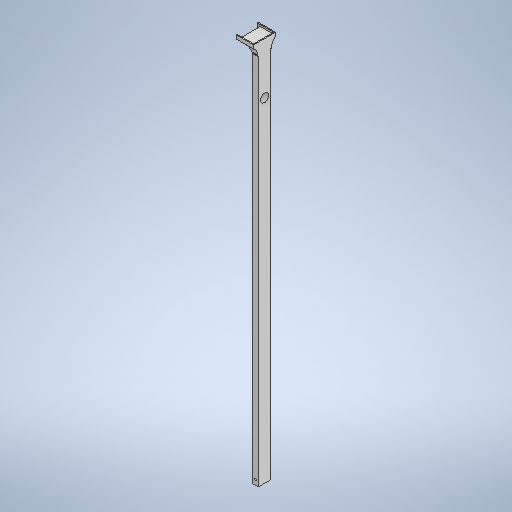
# Autodesk Inventor part: iterasi3-cetak
Saved by Autodesk Inventor 2026.2 (Build 302298010, 298A)
## iProperties
Created: 2026-11-17
Part Number: iterasi3-cetak
Material: Generic
Document SubType Name: Modeling
Designer: Acer
Density: 1 g/cm^3
Appearance: Default
Author: Acer
Autodesk Inventor part; units mm, degrees
ref_plane "YZ Plane" through (0, 0, 0) normal (1, 0, 0) x (0, 1, 0)
ref_plane "XZ Plane" through (0, 0, 0) normal (0, 1, 0) x (-1, 0, 0)
ref_plane "XY Plane" through (0, 0, 0) normal (0, 0, 1) x (1, 0, 0)
sketch "Sketch1" plane through (0, 0, 0) normal (1, 0, 0) x (0, 1, 0)
  line L0 (200, 7) -> (-200, 7)
  line L1 (-200, 7) -> (-200, -7)
  line L2 (-200, -7) -> (200, -7)
  line L3 (200, -7) -> (200, 7)
  line L4 (100, 0) -> (150, 0)
  circle A0 centre (150, 0) radius 4.3
  point P0 (0, 0)
  dimension "d2" = 14
  dimension "d60" = 50
  dimension "d61" = 8.6
  constraints: 10 end point, 3 parallel, 1 centre point, 1 coincident, 1 horizontal, 1 perpendicular
  measures "d2" distance of L1.end L0.end
  measures "d60" distance of L4.start L4.end
  measures "d61" diameter of A0
extrude "Extrusion1" add sketch "Sketch1" along normal blind 6 contours L3 L2 L1 L0 | A0
sketch "Sketch16" plane through (6, 0, 0) normal (1, 0, 0) x (0, 0, -1)
  line L0 (-7, 200) -> (-7, -200) projected
  line L1 (-7, 0) -> (7, 0)
  line L2 (7, -200) -> (7, 200) projected
  line L3 (-7, 0) -> (7, 0)
  line L4 (7, 0) -> (7, -200)
  line L5 (7, -200) -> (-7, -200)
  line L6 (-7, -200) -> (-7, 0)
  point P0 (0, 0)
  constraints: 10 end point, 2 midpoint, 2 parallel, 1 horizontal, 1 perpendicular
extrude "Extrusion11" cut sketch "Sketch16" against normal blind 10
sketch "Sketch18" plane through (0, 200, 7) normal (0, 1, 0) x (1, 0, 0)
  line L0 (0, 14) -> (0, 0) projected
  line L1 (0, 0) -> (6, 0) projected
  line L2 (6, 14) -> (6, 0) projected
  line L3 (0, 14) -> (6, 14) projected
  line L4 (6, -4.5) -> (6, 18.5)
  line L5 (6, 18.5) -> (-12, 18.5)
  line L6 (-12, 18.5) -> (-12, -4.5)
  line L7 (-12, -4.5) -> (6, -4.5)
  line L8 (-12, 18.5) -> (-12, 17.5)
  line L9 (-12, 17.5) -> (-9, 17.5)
  line L10 (0, 7) -> (6, 7)
  line L11 (1, 4.5) -> (1, 9.5) projected
  line L12 (-12, -4.5) -> (-12, -3.5)
  line L13 (-12, -3.5) -> (-9, -3.5)
  line L14 (-9, 17.5) -> (-9, -3.5)
  dimension "d50" = 23
  dimension "d51" = 18
  dimension "d52" = 1
  dimension "d53" = 3
  constraints: 20 end point, 3 perpendicular, 2 horizontal, 2 midpoint, 2 symmetric about line, 2 vertical, 1 point on line
  measures "d50" distance of L4.start L4.end
  measures "d51" distance of L4.end L5.end
  measures "d52" distance of L5.end L8.end
  measures "d53" distance of L8.end L9.end
extrude "Extrusion13" add sketch "Sketch18" along normal blind 2 contours L3 L2 L10 L0 | L0 L1 L4 L7 L6 L13 L14 L9 L5 L3 | L10 L2 L1 L0
sketch "Sketch19" plane through (0, 202, 7) normal (0, 1, 0) x (1, 0, 0)
  line L0 (6, 18.5) -> (-12, 18.5) projected
  line L1 (-12, 18.5) -> (-12, 17.5) projected
  line L2 (-12, 17.5) -> (-9, 17.5) projected
  line L3 (-9, 17.5) -> (-9, -3.5) projected
  line L4 (-9, -3.5) -> (-12, -3.5) projected
  line L5 (-12, -3.5) -> (-12, -4.5) projected
  line L6 (-12, -4.5) -> (6, -4.5) projected
  line L7 (6, -4.5) -> (6, 18.5) projected
  line L8 (-12, 18.5) -> (6, 18.5)
  line L9 (6, 18.5) -> (6, 17.5)
  line L10 (5, 17.5) -> (-12, 17.5)
  line L11 (-12, 17.5) -> (-12, 18.5)
  line L12 (-12, -3.5) -> (5, -3.5)
  line L13 (6, -3.5) -> (6, -4.5)
  line L14 (6, -4.5) -> (-12, -4.5)
  line L15 (-12, -4.5) -> (-12, -3.5)
  line L16 (6, -4.5) -> (6, 18.5) projected
  line L17 (6, 18.5) -> (5, 18.5)
  line L18 (5, 17.5) -> (5, -3.5)
  line L19 (5, -4.5) -> (6, -4.5)
  line L20 (6, -4.5) -> (6, 18.5)
  point P0 (0, 7)
  dimension "d56" = 1
  constraints: 24 end point, 6 parallel, 3 horizontal, 3 perpendicular, 3 point on line
  measures "d56" distance of L19.end L19.start
extrude "Extrusion14" add sketch "Sketch19" along normal blind 1.8 contours L7 L6 L5 L4 L12 L18 L10 L2 L1 L0
fillet "Fillet1" radius 10 3 edges at (3, 200, -7) (0, 200, 0) (3, 200, 7)
sketch "Sketch20" plane through (6, 0, 0) normal (1, 0, 0) x (0, 0, -1)
  line L0 (10.5, 200) -> (-10.5, 200) projected
  line L1 (0, 200) -> (0, 150)
  circle A0 centre (0, 150) radius 4.3
  point P0 (0, 0)
  dimension "d62" = 50
  dimension "d63" = 8.6
  constraints: 2 end point, 1 centre point, 1 coincident, 1 midpoint, 1 vertical
  measures "d62" distance of L1.start L1.end
  measures "d63" diameter of A0
extrude "Extrusion15" cut sketch "Sketch20" against normal blind 8.6
sketch "Sketch21" plane through (6, 0, -7) normal (0, -1, 0) x (1, 0, 0)
  line L0 (-6, 0) -> (-6, 14) projected
  line L1 (0, 0) -> (-6, 0) projected
  line L2 (0, 14) -> (0, 0) projected
  line L3 (-6, 14) -> (0, 14) projected
  point P0 (-6, 7)
extrude "Extrusion16" add sketch "Sketch21" along normal blind 200
sketch "Sketch22" plane through (0, -200, 7) normal (0, 0, 1) x (1, 0, 0)
  line L0 (-0.1285, 391.6484) -> (6, 391.6484) projected
  arc A0 (0, 390.0501) -> (-0.1285, 391.6484) centre (-10, 390.0501) ccw projected
  line L1 (0, 390.0501) -> (0, 0) projected
  line L2 (6, 0) -> (0, 0) projected
  line L3 (6, 391.6484) -> (6, 0) projected
  line L4 (3, 0) -> (3, 5)
  circle A1 centre (3, 5) radius 1.075
  point P0 (0, 200)
  dimension "d68" = 5
  dimension "d69" = 2.15
  constraints: 2 end point, 1 centre point, 1 coincident, 1 midpoint, 1 vertical
  measures "d68" distance of L4.start L4.end
  measures "d69" diameter of A1
extrude "Extrusion17" cut sketch "Sketch22" against normal through all contours A1
sketch "Sketch23" plane through (6, 0, 0) normal (1, 0, 0) x (0, 0, -1)
  line L0 (-7, -200) -> (7, -200) projected
  line L1 (6.5, -200) -> (-6.5, -200)
  line L2 (6.5, 191.6484) -> (-6.5, 191.6484)
  line L3 (-6.5, 191.6484) -> (6.5, 191.6484)
  line L4 (6.5, 191.6484) -> (6.5, -200)
  line L5 (6.5, -200) -> (-6.5, -200)
  line L6 (-6.5, -200) -> (-6.5, 191.6484)
  line L7 (-6.5, 191.6484) -> (-7, 191.6484)
  line L8 (-7, 191.6484) -> (-7, -200)
  line L9 (-6.5, -200) -> (-7, -200)
  line L10 (6.5, -200) -> (7, -200)
  line L11 (6.5, 191.6484) -> (7, 191.6484)
  line L12 (7, 191.6484) -> (7, -200)
  point P0 (0, 0)
  point P1 (0, -200)
  dimension "d72" = 13
  constraints: 24 end point, 4 perpendicular, 3 equal length, 3 horizontal, 2 midpoint, 2 point on line
  measures "d72" distance of L1.start L1.end
extrude "Extrusion18" cut sketch "Sketch23" against normal blind 10 contours L8 L7 L6 L0 | L4 L11 L12 L0
fillet "Fillet2" radius 2 4 edges at (2.9357, 191.6484, -6.5) (2.9357, 191.6484, 6.5) (2.9357, 191.6484, 7) (2.9357, 191.6484, -7)
sketch "Sketch24" plane through (0, 0, 0) normal (-1, 0, 0) x (0, 0, 1)
  line L0 (-6.5, 190.0501) -> (-6.5, -200) projected
  line L1 (6.5, -200) -> (-6.5, -200) projected
  line L2 (6.5, -200) -> (6.5, 190.0501) projected
  line L3 (-6.5, 190.0501) -> (6.5, 190.0501) projected
  circle A0 centre (0, 150) radius 4.3 projected
  circle A1 centre (0, 150) radius 4.45
  point P0 (0, 0)
  dimension "d76" = 8.9
  constraints: 1 centre point, 1 coincident
  measures "d76" diameter of A1
extrude "Extrusion19" cut sketch "Sketch24" against normal through all contours A0 | A1
equation "\"d64\" = d63"
body "Solid1"
